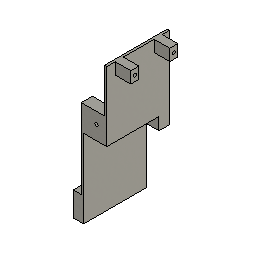
Coco_BladeHolder (Autodesk Fusion 360 design; units mm, degrees)
Autodesk Fusion 360 part; units mm, degrees
sketch "Sketch1" plane through (0, 0, 0) normal (1, 0, 0) x (0, 1, 0)
  line L0 (0, 0) -> (54.3, 0)
  line L1 (54.3, 0) -> (54.3, -60)
  line L2 (54.3, -60) -> (0, -60)
  line L3 (0, -60) -> (0, 0)
  line L4 (7.35, 0) -> (14.35, 0)
  line L5 (14.35, 0) -> (14.35, -10)
  line L6 (14.35, -10) -> (7.35, -10)
  line L7 (7.35, -10) -> (7.35, 0)
  line L8 (41.05, 0) -> (48.05, 0)
  line L9 (48.05, 0) -> (48.05, -10)
  line L10 (48.05, -10) -> (41.05, -10)
  line L11 (41.05, -10) -> (41.05, 0)
  circle A0 centre (10.825, -5) radius 1.35
  circle A1 centre (44.525, -5) radius 1.35
  line L12 (54.3, -60) -> (45.2, -60)
  line L13 (45.2, -60) -> (45.2, -70.7)
  line L14 (45.2, -70.7) -> (54.3, -70.7)
  line L15 (54.3, -70.7) -> (54.3, -60)
  dimension "d1" = 54.3
  dimension "d2" = 60
  dimension "d5" = 7.35
  dimension "d6" = 7
  dimension "d7" = 10
  dimension "d8" = 26.7
  dimension "d9" = 7
  dimension "d10" = 10
  dimension "d11" = 2.7
  dimension "d12" = 5
  dimension "d13" = 2.7
  dimension "d14" = 5
  dimension "d15" = 3.525
  dimension "d16" = 3.525
  dimension "d17" = 10.7
  dimension "d18" = 9.1
  constraint horizontal L0
  constraint vertical L1
  constraint horizontal L2
  constraint vertical L3
  constraint coincident L0.start L3.end
  constraint horizontal L4
  constraint vertical L5
  constraint horizontal L6
  constraint vertical L7
  constraint coincident L0 L4.start
  constraint horizontal L8
  constraint vertical L9
  constraint horizontal L10
  constraint vertical L11
  constraint coincident L0 L8.start
  constraint horizontal L12
  constraint vertical L13
  constraint horizontal L14
  constraint vertical L15
  measures "d1" distance of L0.start L0.end
  measures "d2" distance of L0.start L2.end
  measures "d5" distance of L3 L7
  measures "d6" distance of L5.end L6.end
  measures "d7" distance of L4.start L6.end
  measures "d8" distance of L5 L11
  measures "d9" distance of L9.end L10.end
  measures "d10" distance of L8.end L9.end
  measures "d11" diameter of A0
  measures "d12" distance of L4 A0.centre
  measures "d13" diameter of A1
  measures "d14" distance of L8 A1.centre
  measures "d15" distance of L5 A0.centre
  measures "d16" distance of L9 A1.centre
  measures "d17" distance of L12.end L13.end
  measures "d18" distance of L13.end L14.end
extrude "Extrude2" add sketch "Sketch1" along normal blind 2 contours L0 L1 L2 L3 L5 L6 L7 L9 L10 L11 L12 | L2 L12 L13 L14 L15
extrude "Extrude3" add sketch "Sketch1" along normal blind 15.5 contours L0 L4 L5 L6 L7 | L0 L8 L9 L10 L11
sketch "Sketch3" plane through (0, 0, 0) normal (1, 0, 0) x (0, 1, 0)
  line L0 (54.3, 0) -> (54.3, -60)
  line L1 (54.3, -60) -> (0, -60)
  line L2 (45.2, -70.7) -> (54.3, -70.7)
  line L3 (54.3, -38) -> (44.65, -38)
  line L4 (44.65, -38) -> (44.65, -58)
  line L5 (44.65, -58) -> (9.65, -58)
  line L6 (9.65, -58) -> (9.65, -38)
  line L7 (9.65, -38) -> (0, -38)
  line L8 (0, -38) -> (0, -60)
  line L9 (45, -60) -> (45.2, -70.7)
  line L10 (54.3, -70.7) -> (54.3, -38)
  line L11 (0, 0) -> (54.3, 0)
  dimension "d64" = 35
  dimension "d65" = 20
  dimension "d66" = 9.65
  dimension "d67" = 38
  constraint coincident L0 L3.start
  constraint perpendicular L0 L3
  constraint perpendicular L3 L4
  constraint perpendicular L4 L5
  constraint perpendicular L5 L6
  constraint perpendicular L6 L7
  constraint coincident L1.end L8.end
  constraint perpendicular L1 L8
  constraint coincident L1 L9.start
  constraint coincident L2.start L9.end
  constraint coincident L2.end L10.start
  measures "d64" distance of L4.end L5.end
  measures "d65" distance of L3.end L4.end
  measures "d66" distance of L3.start L3.end
  measures "d67" distance of L3 L11
extrude "Extrude4" add sketch "Sketch3" sketch "Sketch1" against normal blind 20 contours L0 L1 L3 L4 L5 L6 L7 L8 L10 of sketch 2 contours L2 L12 L13 L14 L15
sketch "Sketch5" plane through (-20, 0, 0) normal (-1, 0, 0) x (0, -1, 0)
  line L0 (-54.3, -38) -> (-54.3, -70.7)
  line L1 (-54.3, -70.7) -> (-45.2, -70.7)
  line L2 (-45.2, -70.7) -> (-45.2, -60)
  line L3 (-45.2, -60) -> (0, -60)
  line L4 (0, -60) -> (0, -38)
  line L5 (-54.3, -58) -> (0, -58)
  line L6 (0, -58) -> (0, -127.9)
  line L7 (0, -127.9) -> (-54.3, -127.9)
  line L8 (-54.3, -127.9) -> (-54.3, -58)
  line L9 (-54.3, -106.9) -> (0, -106.9)
  line L10 (0, -106.9) -> (0, -127.9)
  line L11 (0, -127.9) -> (-54.3, -127.9)
  line L12 (-54.3, -127.9) -> (-54.3, -106.9)
  line L13 (-24.0284, -106.9) -> (-32.1113, -106.9)
  line L14 (-34.15, -106.9) -> (-27.15, -113.9)
  line L15 (-27.15, -113.9) -> (-20.15, -106.9)
  line L16 (-44.65, -38) -> (-54.3, -38)
  line L17 (0, -38) -> (-9.65, -38)
  line L18 (-9.65, -38) -> (-9.65, -58)
  line L19 (-9.65, -58) -> (-44.65, -58)
  line L20 (-44.65, -58) -> (-44.65, -38)
  dimension "d38" = 69.9
  dimension "d39" = 21
  dimension "d42" = 14
  dimension "d43" = 14
  dimension "d44" = 20.15
  dimension "d68" = 69.9
  constraint horizontal L5
  constraint vertical L6
  constraint horizontal L7
  constraint vertical L8
  constraint coincident L0 L5.start
  constraint vertical L10
  constraint horizontal L11
  constraint vertical L12
  constraint coincident L8 L9.start
  constraint coincident L9 L13.end
  constraint coincident L9 L13.start
  constraint coincident L9 L14.start
  constraint coincident L9 L15.end
  constraint perpendicular L14 L15
  measures "d38" distance of L5.start L7.end
  measures "d39" distance of L9.start L7.end
  measures "d42" distance of L11 L14.end
  measures "d43" distance of L14.start L15.end
  measures "d44" distance of L9.start L14.start
  measures "d68" distance of L11 L19
extrude "Extrude7" add sketch "Sketch5" against normal blind 2 contours L0 L1 L2 L3 L4 L5 L6 L8 L19 | L1 L2 L3 L6 L8 L9 L13 | L6 L7 L8 L9 L10 L11 L12 L14 L15 | L9 L13 L14 L15
extrude "Extrude8" add sketch "Sketch5" along normal blind 7 contours L6 L7 L8 L9 L10 L11 L12 L14 L15
extrude "Extrude9" add sketch "Sketch5" along normal blind 9 contours L9 L13 L14 L15
sketch "Sketch6" plane through (-27, 0, 0) normal (-1, 0, 0) x (0, -1, 0)
  line L0 (-27.15, -113.9) -> (-34.15, -106.9)
  line L1 (-34.15, -106.9) -> (-54.3, -106.9)
  line L2 (-54.3, -106.9) -> (-54.3, -127.9)
  line L3 (-54.3, -127.9) -> (0, -127.9)
  line L4 (0, -127.9) -> (0, -106.9)
  line L5 (0, -106.9) -> (-20.15, -106.9)
  line L6 (-20.15, -106.9) -> (-27.15, -113.9)
  circle A0 centre (-41.45, -119.9) radius 3.125
  circle A1 centre (-13.95, -119.9) radius 3.125
  dimension "d52" = 6.25
  dimension "d53" = 12.85
  dimension "d54" = 8
  dimension "d69" = 6.25
  measures "d52" diameter of A0
  measures "d53" distance of L2 A0.centre
  measures "d54" distance of L3 A0.centre
  measures "d69" diameter of A1
extrude "Extrude10" cut sketch "Sketch6" against normal blind 3 contours A0 | A1
sketch "Sketch7" plane through (0, 54.3, 0) normal (0, 1, 0) x (-1, 0, 0)
  line L0 (20, -106.9) -> (20, -38)
  line L1 (0, -38) -> (0, 0)
  line L2 (0, 0) -> (-2, 0)
  line L3 (-2, 0) -> (-2, -70.7)
  line L4 (-2, -70.7) -> (18, -70.7)
  line L5 (18, -70.7) -> (18, -127.9)
  line L6 (18, -127.9) -> (27, -127.9)
  line L7 (27, -127.9) -> (27, -106.9)
  line L8 (27, -106.9) -> (20, -106.9)
  circle A0 centre (6.8, -45.4) radius 1.35
  circle A1 centre (6.8, -63.3) radius 1.35
  line L9 (20, -38) -> (0, -38)
  dimension "d58" = 2.7
  dimension "d60" = 8.8
  dimension "d61" = 2.7
  dimension "d70" = 7.4
  dimension "d71" = 17.9
  measures "d58" diameter of A0
  measures "d60" distance of L3 A0.centre
  measures "d61" diameter of A1
  measures "d70" distance of L4 A1.centre
  measures "d71" distance of A0.centre A1.centre
sketch "Sketch8" plane through (0, 9.65, 0) normal (0, 1, 0) x (-1, 0, 0)
  line L0 (0, -38) -> (0, -58)
  line L1 (0, -58) -> (20, -58)
  line L2 (20, -58) -> (20, -38)
  line L3 (20, -38) -> (0, -38)
  circle A0 centre (6.9, -47.8) radius 1.35
  dimension "d73" = 2.7
  dimension "d74" = 9.8
  dimension "d75" = 13.1
  measures "d73" diameter of A0
  measures "d74" distance of L3 A0.centre
  measures "d75" distance of L2 A0.centre
extrude "Extrude11" cut sketch "Sketch7" against normal blind 10 contours A0 | A1
extrude "Extrude12" cut sketch "Sketch8" against normal blind 10 contours A0
sketch "Sketch13" plane through (0, 45.2, 0) normal (0, -1, 0) x (1, 0, 0)
  circle A0 centre (-6.8, -63.3) radius 1.35
  line L0 (-18, -60) -> (-18, -70.7)
  line L1 (-18, -70.7) -> (2, -70.7)
  line L2 (2, -70.7) -> (2, -60)
  line L3 (2, -60) -> (-18, -60)
  line L4 (-18, -60) -> (-18, -80)
  line L5 (-18, -80) -> (2, -60)
  line L6 (2, -60) -> (-18, -60)
  line L7 (2, -60) -> (-18, -60)
  line L8 (-18, -80) -> (-18, -60)
  dimension "d82" = 20
  constraint coincident L0.start L3.end
  constraint perpendicular L1 L4
  constraint coincident L2.end L3.start
  measures "d82" distance of L0.start L4.end
extrude "Extrude13" add sketch "Sketch13" along normal blind 23.25 contours A0 | L0 L1 L3 L4 L5 L6 L7 L8 | L1 L4 L5 L8
extrude "Extrude14" cut sketch "Sketch13" along normal blind 12 contours A0 | L0 L1 L3 L4 L5 L6 L7 L8 | L1 L4 L5 L8
